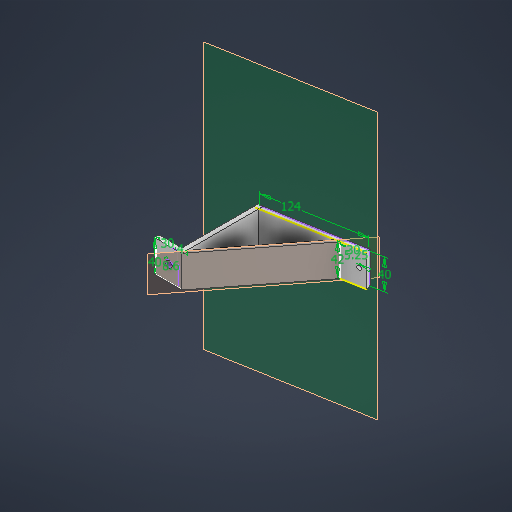
# Autodesk Inventor part: depth_cam_mount_NEWW
Saved by Autodesk Inventor 2026 (Build 300175000, 175)
## iProperties
Created: 2026-09-21
Part Number: depth_cam_mount_NEWW
Material: Generic
Document SubType Name: Modeling
Designer: Nitro
Density: 1 g/cm^3
Appearance: Default
Author: Nitro
Autodesk Inventor part; units mm, degrees
ref_plane "YZ Plane" through (0, 0, 0) normal (1, 0, 0) x (0, 1, 0)
ref_plane "XZ Plane" through (0, 0, 0) normal (0, 1, 0) x (-1, 0, 0)
ref_plane "XY Plane" through (0, 0, 0) normal (0, 0, 1) x (1, 0, 0)
sketch "Sketch1" plane through (0, 0, 0) normal (0, 0, 1) x (1, 0, 0)
  line L0 (0, 0) -> (-30, 0)
  line L1 (-30, 0) -> (-30, 40)
  line L2 (-30, 40) -> (0, 40)
  line L3 (0, 40) -> (0, 0)
  line L4 (0, 40) -> (0, 0)
  line L5 (0, 0) -> (4, 0)
  line L6 (4, 40) -> (0, 40)
  line L7 (0, 40) -> (0, 0)
  line L8 (4, 40) -> (4, 0)
  line L9 (0, 40) -> (-12, 40)
  circle A0 centre (-12, 20) radius 4.3
  dimension "d0" = 30
  dimension "d1" = 40
  dimension "d14" = 4
  dimension "d48" = 8.6
  constraints: 20 end point, 3 parallel, 2 horizontal, 1 centre point, 1 perpendicular, 1 point on line
  measures "d0" distance of L1.end L2.end
  measures "d1" distance of L0.end L1.end
  measures "d14" distance of L6.end L6.start
  measures "d48" diameter of A0
extrude "Extrusion5" add sketch "Sketch1" against normal blind 4 contours L0 L1 L2 L3 | A0
extrude "Extrusion6" add sketch "Sketch1" against normal blind 105 contours L3 L6 L8 L5
extrude "Extrusion7" [suppressed]
extrude "Extrusion8" [suppressed]
ref_plane "Work Plane2" through (0, 40, -105) normal (-0.1736482, 0, -0.9848078) x (0, 1, 0)
sketch "Sketch9" plane through (0, 40, -105) normal (-0.1736482, 0, -0.9848078) x (0, 1, 0)
  line L0 (-0.3663, 1.6764) -> (-40.3663, 1.6764)
  line L1 (-40.3663, 1.6764) -> (-40.3663, 125.6764)
  line L2 (-40.3663, 125.6764) -> (-0.3663, 125.6764)
  line L3 (-0.3663, 125.6764) -> (-0.3663, 1.6764)
  circle A0 centre (-20.3663, 118.126) radius 2.625
  point P0 (-40, -18.2331)
  dimension "d35" = 40
  dimension "d36" = 124
  dimension "d39" = 5.25
  constraints: 8 end point, 2 parallel, 1 centre point, 1 horizontal, 1 perpendicular
  measures "d35" distance of L1.end L2.end
  measures "d36" distance of L2.end L0.start
  measures "d39" diameter of A0
extrude "Extrusion9" add sketch "Sketch9" against normal blind 4 contours L0 L1 L2 L3 | A0
extrude "Extrusion10" add sketch "Sketch9" along normal blind 5 and the other way blind 5 contours A0
shell "Shell2" thickness 1 outward yes removed faces 4 at (116.447, 20.2887, -130.6099) at (114.7393, 22.0487, -128.6164) at (118.1835, 20.2887, -120.7618) at (116.3231, 22.1236, -120.7722)
sketch "Sketch10" plane through (0, 0, 1) normal (0, 0, 1) x (1, 0, 0)
  circle A0 centre (-12.0448, 20.0274) radius 4.2955
  point P0 (0, 0)
  constraints: 1 centre point
extrude "Extrusion12" cut sketch "Sketch10" against normal blind 6
thicken "Thicken1" operation add thickness 5 both sides no extend neighbours no toward (0, 0, -1) faces at (-26.1134, 20.0091, 1)
thicken "Thicken2" operation add thickness 5 both sides no extend neighbours no toward (0.1736482, 0, 0.9848078) faces at (38.1921, 19.7392, -112.7497)
thicken "Thicken3" operation add thickness 6 both sides no extend neighbours no toward (-1, 0, 0) faces at (5, 26.8779, -32.9348)
sketch "Sketch12" plane through (0.8682, 40, -100.076) normal (0.1736482, 0, 0.9848078) x (0.9848078, 0, -0.1736482)
  point P0 (-18.2331, -40)
sketch "Sketch13" plane through (0.8682, 40, -100.076) normal (0.1736482, 0, 0.9848078) x (0.9848078, 0, -0.1736482)
  line L0 (0.6764, 0.6337) -> (126.6764, 0.6337) projected
  line L1 (126.6764, 0.6337) -> (96.6764, 0.6337)
  line L2 (96.6764, 0.6337) -> (96.6764, -41.3663)
  line L3 (126.6764, -41.3663) -> (0.6764, -41.3663) projected
  point P0 (-18.2331, -40)
  dimension "d63" = 30
  dimension "d64" = 42
  constraints: 4 end point, 2 point on line
  measures "d63" distance of L0.end L1.end
  measures "d64" distance of L1.end L2.end
ref_plane "Work Plane4" through (5, 30, 1) normal (0.7912869, 0, 0.611445) x (0, -1, 0)
sketch "Sketch14" plane through (5, 30, 1) normal (0.7912869, 0, 0.611445) x (0, -1, 0)
  line L0 (-11, 0) -> (-11, -22.012) projected
  line L1 (31.3663, 175.1772) -> (31.3663, 81.9925) projected
  line L2 (-10.6337, 171.1387) -> (-10.6337, 80.5566) projected
  line L3 (-10.6337, 148.9878) -> (31.3833, 148.9616)
  line L4 (31, -22.012) -> (31, 0) projected
  line L5 (31.3833, 148.9616) -> (31, 0)
  line L6 (31, 0) -> (-11, 0)
  line L7 (-10.6337, 148.9878) -> (-11, 0)
  point P0 (30, -2.2659)
  point P1 (31.3663, 142.361)
  point P2 (31.3663, 148.9616)
  constraints: 8 end point, 1 perpendicular, 1 point on line
extrude "Extrusion13" add sketch "Sketch14" against normal blind 4 contours L1 L5 L6 L7 L3
body "Solid3"
